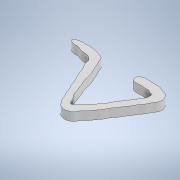
# Autodesk Inventor part: litera_s
Saved by Autodesk Inventor 2022.6 (Build 266554000, 554)
## iProperties
Created: 2024-11-29
Part Number: litera_s
Material: Generic
Document SubType Name: Modeling
Designer: Dragos Macovei
Density: 1 g/cm^3
Appearance: Default
Author: Dragos Macovei
Autodesk Inventor part; units mm, degrees
ref_plane "YZ Plane" through (0, 0, 0) normal (1, 0, 0) x (0, 1, 0)
ref_plane "XZ Plane" through (0, 0, 0) normal (0, 1, 0) x (-1, 0, 0)
ref_plane "XY Plane" through (0, 0, 0) normal (0, 0, 1) x (1, 0, 0)
sketch "Sketch1" plane through (0, 0, 0) normal (0, 1, 0) x (-1, 0, 0)
  line L0 (0, 0) -> (40, 0)
  line L1 (40, 0) -> (40, 40)
  line L2 (40, 40) -> (0, 40)
  line L3 (0, 40) -> (0, 0)
  line L4 (-200.3036, 413.4278) -> (206.0964, 413.4278) construction
  line L5 (206.0964, 413.4278) -> (206.0964, -128.4389) construction
  line L6 (206.0964, -128.4389) -> (-200.3036, -128.4389) construction
  line L7 (-200.3036, -128.4389) -> (-200.3036, 413.4278) construction
  spline S0 degree 5 poles (15.7144, 15.2472) (15.807, 15.1186) (15.9035, 14.8834) (15.9258, 14.4751) (16.0052, 13.6923) (15.5687, 13.3731) (14.8439, 13.0341) (14.3379, 12.7347) (12.6686, 12.7465) (11.4513, 12.9374) (9.9167, 12.9955) (8.4059, 12.8433) (7.6102, 13.3927) (6.3668, 13.9999) (5.7063, 13.7712) (4.7978, 14.8552) (4.2702, 15.7065) (4.045, 16.5988) (4.1383, 17.5111) (4.7214, 18.6849) (5.0906, 18.8026) (5.9292, 20.7397) (6.1472, 21.1212) (7.3438, 22.3634) (7.3477, 22.9943) (8.7757, 24.9862) (9.1503, 25.4571) (9.8142, 26.9973) (11.2224, 28.3074) (11.4896, 29.2904) (12.4658, 31.1066) (13.2745, 31.5247) (13.763, 32.8961) (14.665, 33.424) (15.4397, 34.3497) (15.9128, 35.0577) (16.3642, 36.3599) (17.5671, 36.4985) (18.2214, 37.0866) (19.9524, 36.6688) (20.7218, 36.4638) (21.3819, 35.2356) (22.6866, 34.1513) (22.8364, 31.8867) (23.5857, 32.2936) (24.1971, 28.8771) (24.9477, 29.0831) (25.3837, 26.957) (25.8583, 26.0093) (26.5687, 24.5581) (27.5341, 22.8028) (27.7034, 21.8892) (28.4543, 19.921) (29.5902, 19.2821) (29.3305, 17.1175) (30.1912, 16.8709) (31.3104, 15.6724) (32.6881, 15.9069) (33.4986, 15.6335) (34.6314, 15.598) (35.4624, 14.8909) (36.3116, 14.9107) (37.097, 15.0953) (38.0465, 14.6795) (38.5301, 14.6345) (39.3581, 13.9908) (38.5759, 13.1307) (37.8938, 13.2418) (37.0696, 12.9338) (36.4389, 12.7532) (35.5555, 12.8943) (34.9832, 13.0373) (33.4037, 12.5244) (32.3144, 13.2278) (30.4466, 13.0519) (29.6382, 13.9246) (27.5894, 14.1223) (28.1466, 15.4756) (26.5482, 16.9868) (26.1993, 19.2399) (25.489, 19.5452) (24.753, 22.1681) (24.5255, 22.7741) (24.1825, 25.0404) (23.2945, 25.8788) (23.2895, 26.8304) (22.3737, 28.6312) (22.0516, 29.713) (21.733, 30.9196) (21.0642, 31.3174) (20.1715, 32.5678) (20.1942, 33.0714) (19.5762, 34.1119) (19.0116, 34.0708) (18.3622, 33.5064) (17.8489, 32.781) (16.2985, 31.1483) (15.1959, 30.3211) (14.1324, 28.5649) (12.6618, 27.0623) (12.387, 25.1991) (10.7034, 23.7555) (10.0498, 22.0812) (9.016, 21.3592) (8.5664, 19.0164) (7.3688, 19.2307) (7.7247, 15.9235) (8.162, 16.9723) (9.2188, 16.3827) (9.3972, 15.6161) (11.201, 16.1514) (11.789, 15.5628) (12.9111, 15.903) (13.8013, 15.8058) (14.7117, 15.8732) (15.3404, 15.6221) (15.6046, 15.3997) (15.7144, 15.2472) knots 0 0 0 0 0 0 0.00807 0.0133 0.019856 0.026973 0.034715 0.043424 0.052774 0.062491 0.071996 0.080798 0.08921 0.097426 0.105466 0.113417 0.121603 0.129454 0.137616 0.145884 0.154323 0.162834 0.172191 0.181214 0.190575 0.200366 0.210401 0.220319 0.230235 0.239949 0.249172 0.258147 0.266623 0.275138 0.283532 0.291822 0.300351 0.308851 0.317363 0.32648 0.336061 0.345262 0.355353 0.365338 0.375052 0.384607 0.394682 0.404474 0.414487 0.424682 0.434958 0.445145 0.454722 0.46435 0.473651 0.48256 0.491158 0.499796 0.507968 0.515812 0.523589 0.531007 0.5381 0.545102 0.552041 0.558922 0.565848 0.572826 0.579781 0.587148 0.59508 0.603765 0.613026 0.62278 0.632284 0.642073 0.652081 0.661966 0.67231 0.682954 0.69349 0.703443 0.713237 0.722944 0.732675 0.741821 0.750827 0.759991 0.768402 0.776358 0.783745 0.790757 0.797502 0.805093 0.813467 0.823087 0.833841 0.84531 0.856832 0.868196 0.879243 0.890076 0.900626 0.910823 0.919944 0.928421 0.936177 0.943866 0.951194 0.959122 0.96734 0.975861 0.983968 0.990435 1 1 1 1 1 1
  point P0 (15.8767, 13.8104)
  point P1 (15.5712, 13.4183)
  point P2 (15.0313, 13.1178)
  point P3 (14.4179, 12.8749)
  point P4 (13.0819, 12.7759)
  point P5 (11.4489, 12.8996)
  point P6 (9.7664, 12.9491)
  point P7 (8.3809, 13.0481)
  point P8 (7.3912, 13.4687)
  point P9 (6.4015, 13.8398)
  point P10 (5.7087, 14.0378)
  point P11 (4.8923, 14.8048)
  point P12 (4.3232, 15.7697)
  point P13 (4.1253, 16.6109)
  point P14 (4.249, 17.5511)
  point P15 (4.6696, 18.4418)
  point P16 (5.0902, 19.0356)
  point P17 (5.8077, 20.4212)
  point P18 (6.3273, 21.2624)
  point P19 (7.0448, 22.1779)
  point P20 (7.5644, 23.1181)
  point P21 (8.5788, 24.7016)
  point P22 (9.1726, 25.617)
  point P23 (9.9149, 26.8541)
  point P24 (11.0035, 28.2892)
  point P25 (11.6716, 29.5263)
  point P26 (12.5623, 30.9613)
  point P27 (13.255, 31.8025)
  point P28 (13.8983, 32.7675)
  point P29 (14.6653, 33.5345)
  point P30 (15.3829, 34.3262)
  point P31 (15.9024, 35.1674)
  point P32 (16.5457, 36.1076)
  point P33 (17.4364, 36.5777)
  point P34 (18.3519, 36.8499)
  point P35 (19.7374, 36.7014)
  point P36 (20.6034, 36.3056)
  point P37 (21.3704, 35.4396)
  point P38 (22.4343, 33.8808)
  point P39 (23.0034, 32.3963)
  point P40 (23.4735, 31.6293)
  point P41 (24.3147, 29.4768)
  point P42 (24.859, 28.6108)
  point P43 (25.3786, 27.25)
  point P44 (25.8735, 25.9881)
  point P45 (26.591, 24.5531)
  point P46 (27.3827, 22.9201)
  point P47 (27.8281, 21.683)
  point P48 (28.5951, 20.1243)
  point P49 (29.3126, 18.8377)
  point P50 (29.6342, 17.4027)
  point P51 (30.2528, 16.6852)
  point P52 (31.4404, 15.9676)
  point P53 (32.6775, 15.7944)
  point P54 (33.6177, 15.6707)
  point P55 (34.6321, 15.4233)
  point P56 (35.5476, 15.0274)
  point P57 (36.3393, 14.9532)
  point P58 (37.1805, 14.9532)
  point P59 (38.0218, 14.7305)
  point P60 (38.6156, 14.4831)
  point P61 (38.9867, 13.9635)
  point P62 (38.6156, 13.3697)
  point P63 (37.875, 13.1557)
  point P64 (37.0938, 12.9574)
  point P65 (36.4174, 12.8292)
  point P66 (35.7294, 12.8758)
  point P67 (35.0531, 12.9225)
  point P68 (33.7832, 12.7931)
  point P69 (32.2536, 13.0197)
  point P70 (30.6106, 13.303)
  point P71 (29.3076, 13.8129)
  point P72 (28.1746, 14.3794)
  point P73 (27.778, 15.2472)
  point P74 (26.8716, 17.0421)
  point P75 (26.0784, 18.9116)
  point P76 (25.5119, 20)
  point P77 (24.8321, 21.8575)
  point P78 (24.4922, 23.1605)
  point P79 (23.9823, 24.9167)
  point P80 (23.4724, 25.9365)
  point P81 (23.1325, 26.8996)
  point P82 (22.4527, 28.5991)
  point P83 (21.9995, 29.9021)
  point P84 (21.6029, 30.8086)
  point P85 (20.9797, 31.5451)
  point P86 (20.2999, 32.5648)
  point P87 (20, 33.3013)
  point P88 (19.4988, 33.9287)
  point P89 (19.0835, 33.979)
  point P90 (18.6053, 33.677)
  point P91 (18.0013, 33.0227)
  point P92 (16.6492, 31.5683)
  point P93 (15.3101, 30.2292)
  point P94 (14.0844, 28.663)
  point P95 (12.9041, 26.938)
  point P96 (12.0416, 25.2357)
  point P97 (10.8159, 23.5561)
  point P98 (9.908, 22.1942)
  point P99 (9.1136, 20.9459)
  point P100 (8.2965, 19.4251)
  point P101 (7.661, 18.1087)
  point P102 (7.9333, 16.6333)
  point P103 (8.3192, 16.6333)
  point P104 (8.9547, 16.4063)
  point P105 (9.5676, 15.9524)
  point P106 (10.9294, 15.907)
  point P107 (11.9281, 15.7708)
  point P108 (12.9041, 15.8162)
  point P109 (13.9028, 15.8389)
  point P110 (15.015, 15.7027)
  dimension "d0" = 40
  dimension "d1" = 40
  constraints: 8 end point, 2 parallel, 1 horizontal, 1 perpendicular, 115 other
  measures "d0" distance of L2.end L1.end
  measures "d1" distance of L1.end L0.end
extrude "Extrusion1" add sketch "Sketch1" along normal blind 3 contours S0
body "Solid1"
